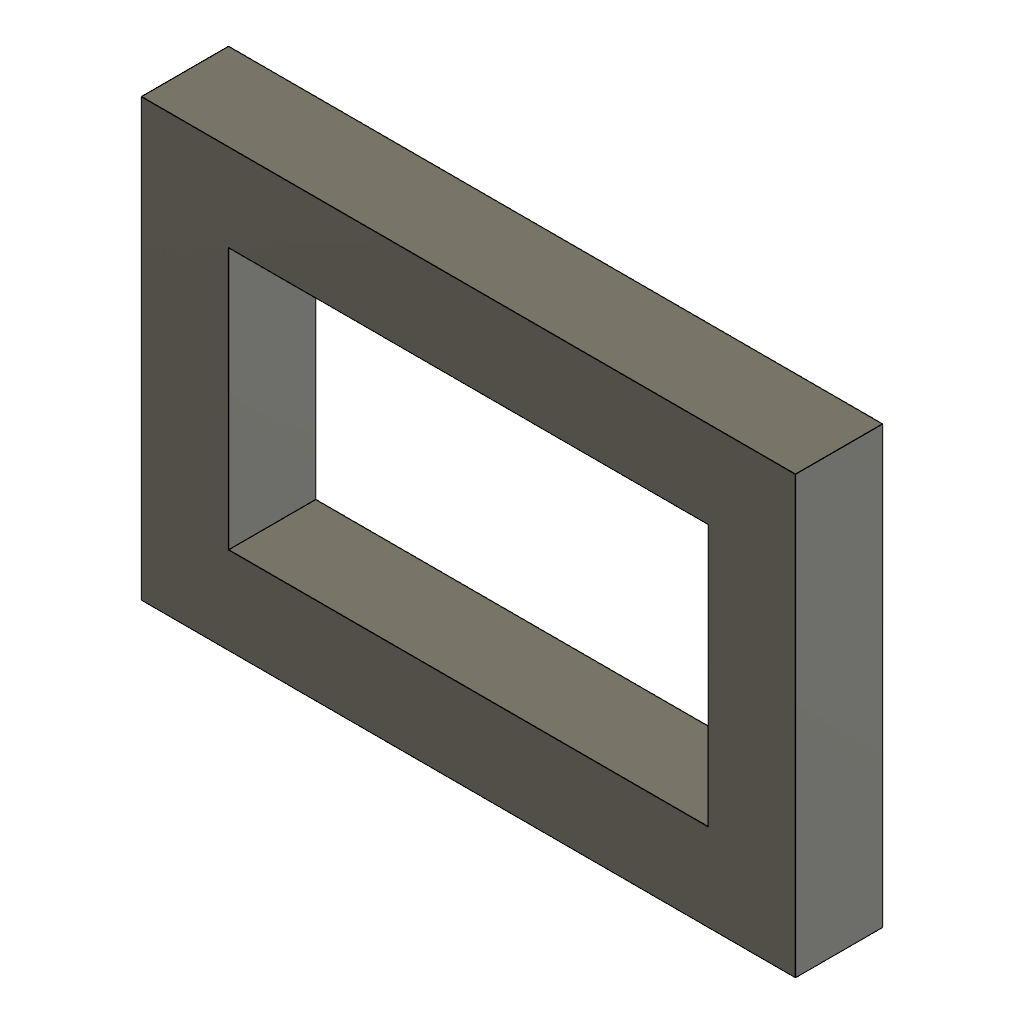
sk_offset_curves_ring (Autodesk Fusion 360 design; units mm, degrees)
part number: 2026-11-13-14-35-07-532
Autodesk Fusion 360 part; units mm, degrees
sketch "Sketch1" plane through (0, 0, 0) normal (0, 0, 1) x (1, 0, 0)
  line L0 (0, 0) -> (30, 0)
  line L1 (30, 0) -> (30, 20)
  line L2 (30, 20) -> (0, 20)
  line L3 (0, 20) -> (0, 0)
  line L4 (26, 4) -> (26, 16)
  line L5 (26, 16) -> (4, 16)
  line L6 (4, 16) -> (4, 4)
  line L7 (4, 4) -> (26, 4)
  dimension "d1" = 4
extrude "Extrude1" add sketch "Sketch1" along normal blind 4
